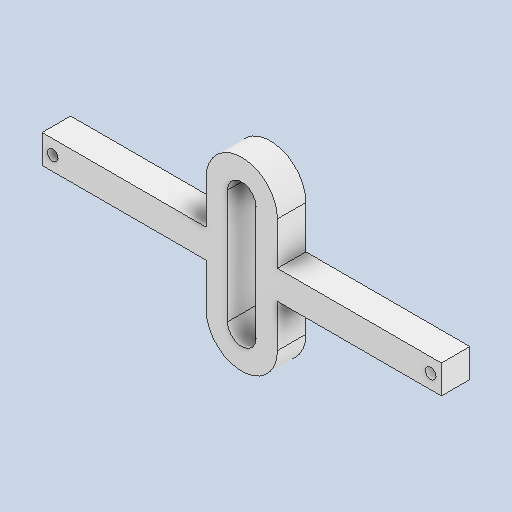
# Autodesk Inventor part: rod
Saved by Autodesk Inventor 2026.1 (Build 301233020, 233B)
## iProperties
Created: 2025-11-26
Part Number: rod
Material: Plastica ABS
Document SubType Name: Modeling
Designer: maxbu
Density: 1.06 g/cm^3
Appearance: Liscia - Bianco
Mass: 1.45194 g
Surface Area: 15.2251 cm^2
Volume: 1.36976 cm^3
Author: maxbu
Autodesk Inventor part; units mm, degrees
ref_plane "YZ Plane" through (0, 0, 0) normal (1, 0, 0) x (0, 1, 0)
ref_plane "XZ Plane" through (0, 0, 0) normal (0, 1, 0) x (-1, 0, 0)
ref_plane "XY Plane" through (0, 0, 0) normal (0, 0, 1) x (1, 0, 0)
sketch "Schizzo1" plane through (0, 0, 0) normal (0, 0, 1) x (1, 0, 0)
  line L0 (0, 0) -> (0, 8) construction
  arc A0 (2, 8) -> (-2, 8) centre (0, 8) ccw
  line L1 (-2, 8) -> (-2, 0)
  line L2 (-5, 2) -> (-5, 8)
  arc A1 (5, 8) -> (-5, 8) centre (0, 8) ccw
  line L3 (5, 8) -> (5, 2)
  line L4 (0, 0) -> (-28, 0) construction
  line L5 (0, 0) -> (28, 0) construction
  line L6 (5, 2) -> (28, 2)
  line L7 (28, 2) -> (28, 0)
  line L8 (-5, 2) -> (-28, 2)
  line L9 (-28, 2) -> (-28, 0)
  line L10 (2, 8) -> (2, 0)
  arc A2 (-2, -8) -> (2, -8) centre (0, -8) ccw
  line L11 (-2, -8) -> (-2, 0)
  line L12 (-5, -2) -> (-5, -8)
  arc A3 (-5, -8) -> (5, -8) centre (0, -8) ccw
  line L13 (5, -8) -> (5, -2)
  line L14 (5, -2) -> (28, -2)
  line L15 (28, -2) -> (28, 0)
  line L16 (-5, -2) -> (-28, -2)
  line L17 (-28, -2) -> (-28, 0)
  line L18 (2, -8) -> (2, 0)
  circle A4 centre (26.5, 0) radius 0.75
  circle A5 centre (-26.5, 0) radius 0.75
  dimension "d0" = 2
  dimension "d2" = 3
  dimension "d3" = 23
  dimension "d5" = 2
  dimension "d6" = 8
  dimension "d7" = 1.5
  dimension "d8" = 1.5
  constraints: 42 end point, 10 symmetric about line, 8 point on circle, 7 perpendicular, 7 point on line, 6 centre point, 4 tangent, 3 horizontal, 2 vertical, 1 coincident, 1 collinear, 3 other
  measures "d0" radius of A0
  measures "d2" radial gap between concentric circles of A0 A1
  measures "d3" distance of L3.end L6.end
  measures "d5" distance from line of L5.end L6
  measures "d6" distance of L0.start L0.end
  measures "d7" diameter of A4
  measures "d8" distance from line of L7 A4.centre
extrude "Estrusione1" add sketch "Schizzo1" along normal blind 4
